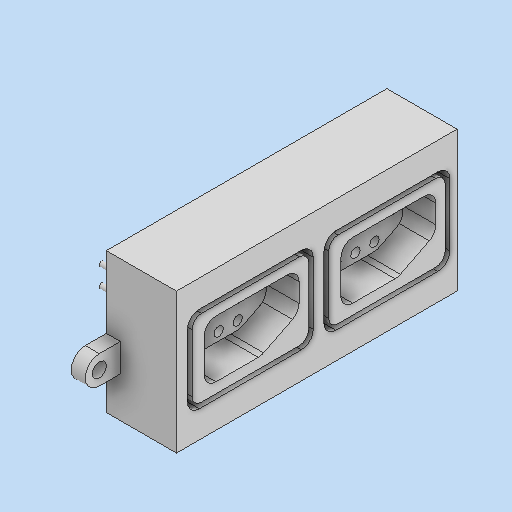
# Autodesk Inventor part: PuertosNes
Saved by Autodesk Inventor 2027 (Build 310192000, 192)
## iProperties
Created: 2026-10-06
Part Number: PuertosNes
Material: Genérico
Document SubType Name: Modeling
Designer: Alexander
Density: 1 g/cm^3
Appearance: Valor por defecto
Author: Alexander
Autodesk Inventor part; units mm, degrees
ref_plane "YZ Plane" through (0, 0, 0) normal (1, 0, 0) x (0, 1, 0)
ref_plane "XZ Plane" through (0, 0, 0) normal (0, 1, 0) x (-1, 0, 0)
ref_plane "XY Plane" through (0, 0, 0) normal (0, 0, 1) x (1, 0, 0)
sketch "Boceto1" plane through (0, 0, 0) normal (1, 0, 0) x (0, 1, 0)
  line L0 (-2.9244, 23.0086) -> (9.5094, 23.0086)
  line L1 (11.5094, 21.0086) -> (11.5094, 0.1086)
  line L2 (9.5094, -1.8914) -> (-2.9244, -1.8914)
  line L3 (-4.9244, 0.1086) -> (-4.9244, 21.0086)
  arc A0 (11.5094, 21.0086) -> (9.5094, 23.0086) centre (9.5094, 21.0086) ccw
  arc A1 (-2.9244, 23.0086) -> (-4.9244, 21.0086) centre (-2.9244, 21.0086) ccw
  arc A2 (-4.9244, 0.1086) -> (-2.9244, -1.8914) centre (-2.9244, 0.1086) ccw
  arc A3 (9.5094, -1.8914) -> (11.5094, 0.1086) centre (9.5094, 0.1086) ccw
  circle A4 centre (5.4134, 16.3855) radius 0.5
  circle A5 centre (5.4134, 16.3855) radius 1
  circle A6 centre (1.3494, 16.3855) radius 0.5
  circle A7 centre (1.3494, 16.3855) radius 1
  circle A8 centre (5.9729, 12.3471) radius 0.5
  circle A9 centre (5.9729, 12.3471) radius 1
  circle A10 centre (1.3494, 12.3215) radius 0.5
  circle A11 centre (1.3494, 12.3215) radius 1
  circle A12 centre (5.4103, 8.2575) radius 0.5
  circle A13 centre (5.4103, 8.2575) radius 1
  circle A14 centre (1.3494, 8.2575) radius 0.5
  circle A15 centre (1.3494, 8.2575) radius 1
  circle A16 centre (5.4103, 4.1935) radius 0.5
  circle A17 centre (5.4103, 4.1935) radius 1
  line L4 (-2.7112, 16.2173) -> (-2.7112, 8.8571)
  line L5 (-0.4414, 16.3855) -> (-0.4414, 8.3563)
  line L6 (9.4774, 16.3855) -> (9.4774, 4.1935)
  line L7 (7.4454, 16.3855) -> (7.4454, 4.1935)
  line L8 (1.3494, 20.4495) -> (7.4454, 20.4495)
  line L9 (7.4454, 20.4495) -> (6.9374, 20.4495)
  line L10 (9.4774, 17.9095) -> (9.4774, 16.3855)
  line L11 (1.3494, 20.4495) -> (-0.1712, 20.4495)
  line L12 (-2.7112, 16.2173) -> (-2.7112, 17.9095)
  line L13 (5.4103, 0.1295) -> (2.9223, 0.1295)
  line L14 (5.4103, 0.1295) -> (6.9374, 0.1295)
  line L15 (9.4774, 2.6695) -> (9.4774, 4.1935)
  line L16 (3.9233, 2.1615) -> (4.9054, 2.1615)
  line L17 (4.9054, 18.4175) -> (2.0986, 18.4175)
  line L18 (-0.4414, 15.8775) -> (-0.4414, 16.3855)
  line L19 (7.4454, 16.3855) -> (7.4454, 15.8775)
  line L20 (7.4454, 4.1935) -> (7.4454, 4.7015)
  line L21 (1.6507, 3.567) -> (-0.1739, 7.2218)
  line L22 (-2.4431, 7.7213) -> (0.6504, 1.5337)
  arc A18 (6.9374, 0.1295) -> (9.4774, 2.6695) centre (6.9374, 2.6695) ccw
  arc A19 (4.9054, 2.1615) -> (7.4454, 4.7015) centre (4.9054, 4.7015) ccw
  arc A20 (7.4454, 15.8775) -> (4.9054, 18.4175) centre (4.9054, 15.8775) ccw
  arc A21 (9.4774, 17.9095) -> (6.9374, 20.4495) centre (6.9374, 17.9095) ccw
  arc A22 (-0.1712, 20.4495) -> (-2.7112, 17.9095) centre (-0.1712, 17.9095) ccw
  arc A23 (2.0986, 18.4175) -> (-0.4414, 15.8775) centre (2.0986, 15.8775) ccw
  arc A24 (-2.7112, 8.8571) -> (-2.4431, 7.7213) centre (-0.1712, 8.8571) ccw
  arc A25 (1.6507, 3.567) -> (3.9233, 2.1615) centre (3.9233, 4.7015) ccw
  arc A26 (-0.4414, 8.3563) -> (-0.1739, 7.2218) centre (2.0986, 8.3563) ccw
  arc A27 (0.6504, 1.5337) -> (2.9223, 0.1295) centre (2.9223, 2.6695) ccw
  line L23 (18.2989, 26.3466) -> (-11.6841, 26.3466)
  line L24 (-11.6841, 26.3466) -> (-11.6841, -33.6534)
  line L25 (-11.6841, -33.6534) -> (18.2989, -33.6534)
  line L26 (18.2989, -33.6534) -> (18.2989, 26.3466)
  line L27 (-2.9917, -6.1914) -> (9.4421, -6.1914)
  line L28 (11.4421, -8.1914) -> (11.4421, -29.0914)
  line L29 (9.4421, -31.0914) -> (-2.9917, -31.0914)
  line L30 (-4.9917, -29.0914) -> (-4.9917, -8.1914)
  arc A28 (11.4421, -8.1914) -> (9.4421, -6.1914) centre (9.4421, -8.1914) ccw
  arc A29 (-2.9917, -6.1914) -> (-4.9917, -8.1914) centre (-2.9917, -8.1914) ccw
  arc A30 (-4.9917, -29.0914) -> (-2.9917, -31.0914) centre (-2.9917, -29.0914) ccw
  arc A31 (9.4421, -31.0914) -> (11.4421, -29.0914) centre (9.4421, -29.0914) ccw
  circle A32 centre (5.3461, -12.8145) radius 0.5
  circle A33 centre (5.3461, -12.8145) radius 1
  circle A34 centre (1.2823, -12.8554) radius 0.5
  circle A35 centre (1.2823, -12.8554) radius 1
  circle A36 centre (5.9056, -16.8785) radius 0.5
  circle A37 centre (5.9056, -16.8785) radius 1
  circle A38 centre (1.2823, -16.9194) radius 0.5
  circle A39 centre (1.2823, -16.9194) radius 1
  circle A40 centre (5.3432, -20.9834) radius 0.5
  circle A41 centre (5.3432, -20.9834) radius 1
  circle A42 centre (1.2823, -20.9834) radius 0.5
  circle A43 centre (1.2823, -20.9834) radius 1
  circle A44 centre (5.3432, -25.0474) radius 0.5
  circle A45 centre (5.3432, -25.0474) radius 1
  line L31 (-2.7782, -13.0236) -> (-2.7782, -20.3839)
  line L32 (-0.5085, -12.8554) -> (-0.5085, -20.8846)
  line L33 (9.4101, -12.8145) -> (9.4101, -25.0065)
  line L34 (7.3777, -12.8554) -> (7.3777, -25.0474)
  line L35 (1.2821, -8.7914) -> (7.3777, -8.7914)
  line L36 (7.3777, -8.7914) -> (6.8701, -8.7914)
  line L37 (9.4101, -11.3314) -> (9.4101, -12.8145)
  line L38 (1.2821, -8.7914) -> (-0.2382, -8.7914)
  line L39 (-2.7782, -13.0236) -> (-2.7782, -11.3314)
  line L40 (5.3432, -29.1114) -> (2.8552, -29.1114)
  line L41 (5.3432, -29.1114) -> (6.8701, -29.1114)
  line L42 (9.4101, -26.5714) -> (9.4101, -25.0065)
  line L43 (3.8562, -27.0794) -> (4.8377, -27.0794)
  line L44 (4.8377, -10.8234) -> (2.0315, -10.8234)
  line L45 (-0.5085, -13.3634) -> (-0.5085, -12.8554)
  line L46 (7.3777, -12.8554) -> (7.3777, -13.3634)
  line L47 (7.3777, -25.0474) -> (7.3777, -24.5394)
  line L48 (1.5837, -25.674) -> (-0.241, -22.0192)
  line L49 (-2.5101, -21.5197) -> (0.5833, -27.7072)
  arc A46 (6.8701, -29.1114) -> (9.4101, -26.5714) centre (6.8701, -26.5714) ccw
  arc A47 (4.8377, -27.0794) -> (7.3777, -24.5394) centre (4.8377, -24.5394) ccw
  arc A48 (7.3777, -13.3634) -> (4.8377, -10.8234) centre (4.8377, -13.3634) ccw
  arc A49 (9.4101, -11.3314) -> (6.8701, -8.7914) centre (6.8701, -11.3314) ccw
  arc A50 (-0.2382, -8.7914) -> (-2.7782, -11.3314) centre (-0.2382, -11.3314) ccw
  arc A51 (2.0315, -10.8234) -> (-0.5085, -13.3634) centre (2.0315, -13.3634) ccw
  arc A52 (-2.7782, -20.3839) -> (-2.5101, -21.5197) centre (-0.2382, -20.3839) ccw
  arc A53 (1.5837, -25.674) -> (3.8562, -27.0794) centre (3.8562, -24.5394) ccw
  arc A54 (-0.5085, -20.8846) -> (-0.241, -22.0192) centre (2.0315, -20.8846) ccw
  arc A55 (0.5833, -27.7072) -> (2.8552, -29.1114) centre (2.8552, -26.5714) ccw
  line L50 (9.9021, -32.0914) -> (-3.4517, -32.0914)
  line L51 (-5.9917, -29.5514) -> (-5.9917, -7.7314)
  line L52 (-3.4517, -5.1914) -> (9.9021, -5.1914)
  line L53 (12.4421, -7.7314) -> (12.4421, -29.5514)
  arc A56 (12.4421, -7.7314) -> (9.9021, -5.1914) centre (9.9021, -7.7314) ccw
  arc A57 (-3.4517, -5.1914) -> (-5.9917, -7.7314) centre (-3.4517, -7.7314) ccw
  arc A58 (-5.9917, -29.5514) -> (-3.4517, -32.0914) centre (-3.4517, -29.5514) ccw
  arc A59 (9.9021, -32.0914) -> (12.4421, -29.5514) centre (9.9021, -29.5514) ccw
  line L54 (9.9694, -2.8914) -> (-3.3844, -2.8914)
  line L55 (-5.9244, -0.3514) -> (-5.9244, 21.4686)
  line L56 (-3.3844, 24.0086) -> (9.9694, 24.0086)
  line L57 (12.5094, 21.4686) -> (12.5094, -0.3514)
  arc A60 (-5.9244, -0.3514) -> (-3.3844, -2.8914) centre (-3.3844, -0.3514) ccw
  arc A61 (9.9694, -2.8914) -> (12.5094, -0.3514) centre (9.9694, -0.3514) ccw
  arc A62 (12.5094, 21.4686) -> (9.9694, 24.0086) centre (9.9694, 21.4686) ccw
  arc A63 (-3.3844, 24.0086) -> (-5.9244, 21.4686) centre (-3.3844, 21.4686) ccw
  point P0 (-4.9244, 23.0086)
  point P1 (-4.9244, -1.8914)
  point P2 (-0.6826, 16.3855)
  point P3 (-0.6826, 16.3855)
  point P4 (1.915, 4.2191)
  point P5 (9.4774, 20.4495)
  point P6 (-2.7112, 20.4495)
  point P7 (7.4454, 18.4175)
  point P8 (7.4454, 18.4175)
  point P9 (7.4454, 2.1615)
  point P10 (-4.9917, -6.1914)
  point P11 (-4.9917, -31.0914)
  point P12 (-0.7497, -12.8554)
  point P13 (-0.7497, -12.8554)
  point P14 (1.8477, -25.0065)
  point P15 (9.4101, -8.7914)
  point P16 (-2.7782, -8.7914)
  point P17 (7.3777, -10.8234)
  point P18 (7.3777, -10.8234)
  point P19 (7.3777, -27.0794)
  point P20 (-0.5085, -13.3634)
  point P21 (7.3777, -13.3634)
  point P22 (3.2252, -32.0914)
  dimension "d5" = 24.9
  dimension "d6" = 2
  dimension "d7" = 4.064
  dimension "d8" = 4.064
  dimension "d9" = 4.064
  dimension "d10" = 4.064
  dimension "d11" = 1
  dimension "d12" = 2
  dimension "d13" = 1
  dimension "d14" = 2
  dimension "d15" = 1
  dimension "d16" = 2
  dimension "d17" = 1
  dimension "d18" = 2
  dimension "d19" = 1
  dimension "d20" = 2
  dimension "d21" = 1
  dimension "d22" = 2
  dimension "d23" = 1
  dimension "d24" = 2
  dimension "d25" = 4.064
  dimension "d27" = 16.4338
  dimension "d28" = 2.032
  dimension "d29" = 2.032
  dimension "d30" = 4.064
  dimension "d31" = 4.064
  dimension "d32" = 2.032
  dimension "d33" = 2.032
  dimension "d34" = 2.54
  dimension "d35" = 4.0605
  dimension "d36" = 2.54
  dimension "d37" = 2.54
  dimension "d38" = 2.54
  dimension "d39" = 2.032
  dimension "d40" = 60
  dimension "d41" = 24.9
  dimension "d42" = 2
  dimension "d43" = 4.064
  dimension "d44" = 4.064
  dimension "d45" = 4.064
  dimension "d46" = 4.064
  dimension "d47" = 1
  dimension "d48" = 2
  dimension "d49" = 1
  dimension "d50" = 2
  dimension "d51" = 1
  dimension "d52" = 2
  dimension "d53" = 1
  dimension "d54" = 2
  dimension "d55" = 1
  dimension "d56" = 2
  dimension "d57" = 1
  dimension "d58" = 2
  dimension "d59" = 1
  dimension "d60" = 2
  dimension "d61" = 4.064
  dimension "d62" = 16.4338
  dimension "d63" = 2.032
  dimension "d64" = 2.032
  dimension "d65" = 4.064
  dimension "d66" = 4.064
  dimension "d67" = 2.032
  dimension "d68" = 2.032
  dimension "d69" = 2.54
  constraints: 116 end point, 72 point on circle, 72 tangent, 64 centre point, 40 coincident, 34 point on line, 24 equal radius, 19 perpendicular, 13 horizontal, 10 parallel, 6 vertical, 1 midpoint
  measures "d5" distance of point (-4.924, -1.891) point (-4.924, 23.009)
  measures "d6" radius of A0
  measures "d7" distance of point (1.349, 12.322) point (1.349, 16.386)
  measures "d8" distance of point (1.349, 8.258) point (1.349, 12.322)
  measures "d9" distance of point (5.413, 16.386) point (1.349, 16.386)
  measures "d10" distance of point (5.41, 4.194) point (5.41, 8.258)
  measures "d11" diameter of A4
  measures "d12" diameter of A5
  measures "d13" diameter of A6
  measures "d14" diameter of A7
  measures "d15" diameter of A8
  measures "d16" diameter of A9
  measures "d17" diameter of A10
  measures "d18" diameter of A11
  measures "d19" diameter of A12
  measures "d20" diameter of A13
  measures "d21" diameter of A14
  measures "d22" diameter of A15
  measures "d23" diameter of A16
  measures "d24" diameter of A17
  measures "d25" distance of L6.start A5.centre
  measures "d27" distance between parallel lines of L1 L3
  measures "d28" distance of point (-0.683, 16.386) A6.centre
  measures "d29" distance of L7.start A4.centre
  measures "d30" distance of L8.start A6.centre
  measures "d31" distance of L13.start A16.centre
  measures "d32" distance between parallel lines of L16 L13
  measures "d33" distance of point (7.445, 18.418) L19.start
  measures "d34" radius of A18
  measures "d35" horizontal distance of L4.start A6.centre
  measures "d36" radius of A19
  measures "d37" radius of A20
  measures "d38" radius of A27
  measures "d39" distance between parallel lines of L1 L6
  measures "d40" distance between parallel lines of L23 L25
  measures "d41" distance of point (-4.992, -31.091) point (-4.992, -6.191)
  measures "d42" radius of A28
  measures "d43" distance of point (1.282, -16.919) point (1.282, -12.855)
  measures "d44" distance of point (1.282, -20.983) point (1.282, -16.919)
  measures "d45" distance of point (5.346, -12.814) point (1.282, -12.855)
  measures "d46" distance of point (5.343, -25.047) point (5.343, -20.983)
  measures "d47" diameter of A32
  measures "d48" diameter of A33
  measures "d49" diameter of A34
  measures "d50" diameter of A35
  measures "d51" diameter of A36
  measures "d52" diameter of A37
  measures "d53" diameter of A38
  measures "d54" diameter of A39
  measures "d55" diameter of A40
  measures "d56" diameter of A41
  measures "d57" diameter of A42
  measures "d58" diameter of A43
  measures "d59" diameter of A44
  measures "d60" diameter of A45
  measures "d61" distance of L33.start A33.centre
  measures "d62" distance between parallel lines of L28 L30
  measures "d63" distance of point (-0.75, -12.855) A34.centre
  measures "d64" distance of L34.start A32.centre
  measures "d65" distance of L38.start A34.centre
  measures "d66" distance of L41.start A44.centre
  measures "d67" distance between parallel lines of L43 L40
  measures "d68" distance of point (7.378, -10.823) L46.start
  measures "d69" radius of A46
extrude "Extrusión1" add sketch "Boceto1" along normal blind 10 contours A23 L17 A20 L7 A19 L16 A25 L21 A26 L5 | A51 L44 A48 L34 A47 L43 A53 L48 A54 L32
extrude "Extrusión2" add sketch "Boceto1" along normal blind 2 contours L12 A22 L11 L8 A21 L10 L6 L15 A18 L14 L13 A27 L22 A24 L4 | L39 A50 L38 L35 A49 L37 L33 L42 A46 L41 L40 A55 L49 A52 L31
extrude "Extrusión3" add sketch "Boceto1" along normal blind 15 contours L0 A0 L1 A3 L2 A2 L3 A1 | L27 A28 L28 A31 L29 A30 L30 A29
extrude "Extrusión4" add sketch "Boceto1" along normal blind 15 contours L26 L25 L24 L23
sketch "Boceto2" plane through (0, 0, 0) normal (-1, 0, 0) x (0, 0, 1)
  line L0 (25.3466, -10.6841) -> (-32.6534, -10.6841)
  line L1 (-32.6534, -10.6841) -> (-32.6534, 17.2989)
  line L2 (-32.6534, 17.2989) -> (25.3466, 17.2989)
  line L3 (25.3466, 17.2989) -> (25.3466, -10.6841)
  line L4 (-33.6534, -11.6841) -> (-33.6534, 18.2989) projected
  line L5 (26.3466, -11.6841) -> (-33.6534, -11.6841) projected
  line L6 (26.3466, 18.2989) -> (26.3466, -11.6841) projected
  line L7 (-33.6534, 18.2989) -> (26.3466, 18.2989) projected
  point P0 (0, 0)
  dimension "d95" = 1
  dimension "d96" = 1
  dimension "d97" = 1
  dimension "d98" = 1
  constraints: 8 end point, 2 parallel, 1 horizontal, 1 perpendicular
  measures "d95" distance between parallel lines of L1 L4
  measures "d96" distance between parallel lines of L5 L0
  measures "d97" distance between parallel lines of L6 L3
  measures "d98" distance between parallel lines of L2 L7
extrude "Extrusión5" add sketch "Boceto2" along normal blind 1 contours L0 L1 L2 L3
sketch "Boceto3" plane through (-1, 0, 0) normal (-1, 0, 0) x (0, 0, 1)
  circle A0 centre (16.3855, 1.3494) radius 1 projected
  circle A1 centre (16.3855, 1.3494) radius 1
  circle A2 centre (12.3215, 1.3494) radius 1 projected
  circle A3 centre (12.3215, 1.3494) radius 1
  circle A4 centre (8.2575, 1.3494) radius 1 projected
  circle A5 centre (8.2575, 1.3494) radius 1
  circle A6 centre (16.3855, 5.4134) radius 1 projected
  circle A7 centre (16.3855, 5.4134) radius 1
  circle A8 centre (12.3471, 5.4134) radius 1
  circle A9 centre (8.2575, 5.4103) radius 1 projected
  circle A10 centre (8.2575, 5.4103) radius 1
  circle A11 centre (4.1935, 5.4103) radius 1 projected
  circle A12 centre (4.1935, 5.4103) radius 1
  arc A13 (18.4175, 4.9054) -> (15.8775, 7.4454) centre (15.8775, 4.9054) ccw projected
  line L0 (18.4175, 4.9054) -> (18.4175, 2.0986) projected
  line L1 (18.4175, 4.9054) -> (18.4175, 2.0986)
  line L2 (15.8775, -0.4414) -> (8.3563, -0.4414) projected
  line L3 (15.8775, -0.4414) -> (8.3563, -0.4414)
  line L4 (4.7015, 7.4454) -> (15.8775, 7.4454) projected
  line L5 (15.8775, 7.4454) -> (4.7015, 7.4454)
  line L6 (7.2218, -0.1739) -> (3.567, 1.6507) projected
  line L7 (7.2218, -0.1739) -> (3.567, 1.6507)
  arc A14 (4.7015, 7.4454) -> (2.1615, 4.9054) centre (4.7015, 4.9054) ccw projected
  arc A15 (2.1615, 3.9233) -> (3.567, 1.6507) centre (4.7015, 3.9233) ccw projected
  line L8 (2.1615, 4.9054) -> (2.1615, 3.9233)
  line L9 (2.1615, 3.9233) -> (2.1615, 4.9054)
  arc A16 (15.8775, -0.4414) -> (18.4175, 2.0986) centre (15.8775, 2.0986) ccw
  arc A17 (7.2218, -0.1739) -> (8.3563, -0.4414) centre (8.3563, 2.0986) ccw
  circle A18 centre (-12.8145, 5.3461) radius 1 projected
  circle A19 centre (-12.8145, 5.3461) radius 1
  circle A20 centre (-16.8785, 5.4103) radius 1
  circle A21 centre (-20.9834, 5.3432) radius 1 projected
  circle A22 centre (-20.9834, 5.3432) radius 1
  circle A23 centre (-25.0474, 5.3432) radius 1 projected
  circle A24 centre (-25.0474, 5.3432) radius 1
  circle A25 centre (-20.9834, 1.2823) radius 1 projected
  circle A26 centre (-20.9834, 1.2823) radius 1
  circle A27 centre (-16.9194, 1.2823) radius 1 projected
  circle A28 centre (-16.9194, 1.2823) radius 1
  circle A29 centre (-12.8554, 1.2823) radius 1 projected
  circle A30 centre (-12.8554, 1.2823) radius 1
  line L10 (-10.8234, 4.8377) -> (-10.8234, 2.0315) projected
  line L11 (-10.8234, 4.8377) -> (-10.8234, 2.0315)
  line L12 (-24.5394, 7.3777) -> (-13.3634, 7.3777) projected
  line L13 (-13.3634, 7.3777) -> (-24.5394, 7.3777)
  line L14 (-13.3634, -0.5085) -> (-20.8846, -0.5085) projected
  line L15 (-13.3634, -0.5085) -> (-20.8846, -0.5085)
  line L16 (-27.0794, 3.8562) -> (-27.0794, 4.8377) projected
  line L17 (-27.0794, 4.8377) -> (-27.0794, 3.8562)
  line L18 (-22.0192, -0.241) -> (-25.674, 1.5837) projected
  line L19 (-25.674, 1.5837) -> (-22.0192, -0.241)
  arc A31 (-10.8234, 4.8377) -> (-13.3634, 7.3777) centre (-13.3634, 4.8377) ccw
  arc A32 (-13.3634, -0.5085) -> (-10.8234, 2.0315) centre (-13.3634, 2.0315) ccw
  arc A33 (-22.0192, -0.241) -> (-20.8846, -0.5085) centre (-20.8846, 2.0315) ccw
  arc A34 (-27.0794, 3.8562) -> (-25.674, 1.5837) centre (-24.5394, 3.8562) ccw
  arc A35 (-24.5394, 7.3777) -> (-27.0794, 4.8377) centre (-24.5394, 4.8377) ccw
  point P0 (0, 0)
  dimension "d101" = 2
  dimension "d102" = 2.54
  dimension "d103" = 2
  dimension "d104" = 2.54
  constraints: 22 end point, 21 centre point, 16 tangent, 14 point on circle, 13 point on line, 12 coincident, 8 collinear, 5 equal radius, 2 vertical, 1 horizontal
  measures "d101" diameter of A8
  measures "d102" radius of A16
  measures "d103" diameter of A20
  measures "d104" radius of A31
extrude "Extrusión6" add sketch "Boceto3" along normal blind 1
sketch "Boceto4" plane through (-1, 1.3494, 16.3855) normal (-1, 0, 0) x (0, 0, 1)
  circle A0 centre (0, 0) radius 1 projected
  circle A1 centre (0, 0) radius 0.5
  circle A2 centre (-4.064, 0) radius 1 projected
  circle A3 centre (-4.064, 0) radius 0.5
  circle A4 centre (-8.128, 0) radius 1 projected
  circle A5 centre (-8.128, 0) radius 0.5
  circle A6 centre (0, 4.064) radius 1 projected
  circle A7 centre (0, 4.064) radius 0.5
  circle A8 centre (-4.0384, 4.064) radius 0.5
  circle A9 centre (-8.128, 4.061) radius 1 projected
  circle A10 centre (-8.128, 4.061) radius 0.5
  circle A11 centre (-12.192, 4.061) radius 1 projected
  circle A12 centre (-12.192, 4.061) radius 0.5
  circle A13 centre (-29.2409, -0.0671) radius 1 projected
  circle A14 centre (-29.2409, -0.0671) radius 0.5
  circle A15 centre (-33.3049, 0) radius 0.5
  circle A16 centre (-37.3689, -0.0671) radius 1 projected
  circle A17 centre (-37.3689, -0.0671) radius 0.5
  circle A18 centre (-29.2, 3.9967) radius 1 projected
  circle A19 centre (-29.2, 3.9967) radius 0.5
  circle A20 centre (-33.264, 3.9967) radius 0.5
  circle A21 centre (-37.3689, 3.9967) radius 0.5
  circle A22 centre (-41.4329, 3.9939) radius 1 projected
  circle A23 centre (-41.4329, 3.9939) radius 0.5
  point P0 (-16.3855, -1.3494)
  dimension "d107" = 1
  dimension "d108" = 1
  dimension "d109" = 1
  dimension "d110" = 1
  dimension "d111" = 1
  dimension "d112" = 1
  dimension "d113" = 1
  dimension "d114" = 1
  dimension "d115" = 1
  dimension "d116" = 1
  dimension "d117" = 1
  dimension "d118" = 1
  dimension "d119" = 1
  dimension "d120" = 1
  constraints: 14 centre point, 10 coincident
  measures "d107" diameter of A1
  measures "d108" diameter of A3
  measures "d109" diameter of A5
  measures "d110" diameter of A7
  measures "d111" diameter of A8
  measures "d112" diameter of A10
  measures "d113" diameter of A12
  measures "d114" diameter of A14
  measures "d115" diameter of A15
  measures "d116" diameter of A17
  measures "d117" diameter of A19
  measures "d118" diameter of A20
  measures "d119" diameter of A21
  measures "d120" diameter of A23
extrude "Extrusión7" add sketch "Boceto4" along normal blind 10 contours A1 | A3 | A5 | A7 | A8 | A10 | A12 | A14 | A15 | A17 | A19 | A20 | A21 | A23
sketch "Boceto5" plane through (0, 0, 0) normal (-1, 0, 0) x (0, 0, 1)
  line L0 (-33.6534, 18.2989) -> (-33.6534, -11.6841)
  line L1 (-33.6534, -11.6841) -> (-33.6534, 18.2989) projected
  line L2 (-33.6534, 18.2989) -> (26.3466, 18.2989) projected
  line L3 (26.3466, 18.2989) -> (26.3466, -11.6841) projected
  line L4 (26.3466, 18.2989) -> (26.3466, -11.6841)
  line L5 (-33.6534, -11.6841) -> (-33.6534, 18.2989) projected
  line L6 (-33.6534, -0.0245) -> (-33.6534, 4.9755)
  line L7 (-33.6534, -0.0245) -> (-33.6534, 3.9755)
  line L8 (-33.6534, 3.9755) -> (-37.1534, 3.9755)
  line L9 (-33.6534, -0.0245) -> (-33.6534, -4.0245)
  line L10 (-33.6534, -4.0245) -> (-37.1534, -4.0245)
  arc A0 (-37.1534, 3.9755) -> (-37.1534, -4.0245) centre (-37.1534, -0.0245) ccw
  line L11 (26.3466, -0.0245) -> (26.3466, 2.9755)
  line L12 (26.3466, -0.0245) -> (26.3466, -3.0245)
  line L13 (26.3466, -3.0245) -> (30.8466, -3.0245)
  line L14 (26.3466, 2.9755) -> (30.8466, 2.9755)
  arc A1 (30.8466, -3.0245) -> (30.8466, 2.9755) centre (30.8466, -0.0245) ccw
  circle A2 centre (-37.1534, -0.0245) radius 1.5
  circle A3 centre (30.8466, -0.0245) radius 1.5
  point P0 (0, 0)
  dimension "d133" = 5
  dimension "d134" = 4
  dimension "d135" = 4
  dimension "d136" = 3.5
  dimension "d137" = 3
  dimension "d138" = 3
  dimension "d139" = 4.5
  dimension "d140" = 3
  dimension "d141" = 3
  constraints: 22 end point, 7 point on line, 4 centre point, 4 point on circle, 4 tangent, 3 perpendicular, 2 coincident, 1 collinear, 1 horizontal
  measures "d133" distance of L6.start L6.end
  measures "d134" distance of L6.start L7.end
  measures "d135" distance of L6.start L9.end
  measures "d136" distance of L9.end L10.end
  measures "d137" distance of L11.start L11.end
  measures "d138" distance of L11.start L12.end
  measures "d139" distance of L12.end L13.end
  measures "d140" diameter of A2
  measures "d141" diameter of A3
extrude "Extrusión10" add sketch "Boceto5" against normal blind 3
